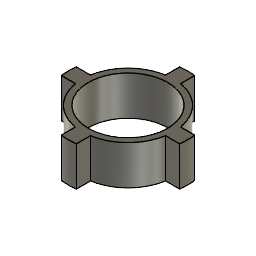
Probe Spacer (Autodesk Fusion 360 design; units mm, degrees)
Autodesk Fusion 360 part; units mm, degrees
sketch "Sketch1" plane through (0, 0, 0) normal (0, 0, 1) x (1, 0, 0)
  circle A0 centre (0, 0) radius 13.125
  circle A1 centre (0, 0) radius 15.125
  circle A2 centre (0, 0) radius 19.75
  line L0 (27.6355, 2.5) -> (-27.6355, 2.5)
  line L1 (-27.6355, 2.5) -> (-27.6355, -2.5)
  line L2 (-27.6355, -2.5) -> (27.6355, -2.5)
  line L3 (27.6355, -2.5) -> (27.6355, 2.5)
  line L4 (27.6355, 2.5) -> (-27.6355, -2.5) construction
  line L5 (-27.6355, 2.5) -> (27.6355, -2.5) construction
  line L6 (2.5, 24) -> (-2.5, 24)
  line L7 (-2.5, 24) -> (-2.5, -24)
  line L8 (-2.5, -24) -> (2.5, -24)
  line L9 (2.5, -24) -> (2.5, 24)
  line L10 (2.5, 24) -> (-2.5, -24) construction
  line L11 (-2.5, 24) -> (2.5, -24) construction
  dimension "d1" = 26.25
  dimension "d2" = 2
  dimension "d3" = 39.5
  dimension "d4" = 5
  dimension "d5" = 5
  constraint coincident A0.centre A1.centre
  constraint concentric A0 A2
  constraint horizontal L0
  constraint perpendicular L0 L1
  constraint parallel L0 L2
  constraint parallel L1 L3
  constraint coincident L4 A0.centre
  constraint coincident L5 A0.centre
  constraint horizontal L6
  constraint perpendicular L6 L7
  constraint parallel L6 L8
  constraint parallel L7 L9
  constraint coincident L10 A0.centre
  constraint coincident L11 A0.centre
  measures "d1" diameter of A0
  measures "d3" diameter of A2
  measures "d4" distance of L0.end L1.end
  measures "d5" distance of L7.end L8.end
extrude "Extrude1" add sketch "Sketch1" along normal blind 13 contours A0 A1 L0 L2 | A0 A1 L0 L9 | A0 A1 L2 L9 | A0 A1 L7 L9 | A1 A2 L0 L2 | A0 A1 L7 L9 | A0 A1 L0 L7 | A1 A2 L7 L9 | A0 A1 L2 L7 | A1 A2 L7 L9 | A0 A1 L0 L2 | A1 A2 L0 L2
